Autodesk Fusion 360 part; units mm, degrees
(part 7 of 7)
sketch "Hex nut (1) (8)" plane through (0, 0, 57.8) normal (0, 0, 1) x (1, 0, 0) in component "HARDWARE | Core M2x50 · unthreaded reference"
  line L0 (2.3094, 42) -> (1.1547, 44)
  line L1 (1.1547, 44) -> (-1.1547, 44)
  line L2 (-1.1547, 44) -> (-2.3094, 42)
  line L3 (-2.3094, 42) -> (-1.1547, 40)
  line L4 (-1.1547, 40) -> (1.1547, 40)
  line L5 (1.1547, 40) -> (2.3094, 42)
extrude "Hex nut (2)'''''''" add sketch "Hex nut (1) (8)" along normal blind 1.6 separate body makes body 121 in component "HARDWARE | Core M2x50 · unthreaded reference"
ref_plane "WorkPlane12" through (0, 0, 57.8) normal (0, 0, 1) x (1, 0, 0) in component "HARDWARE | Core M2x50 · unthreaded reference"
sketch "Nut thread envelope clearance (1) (9)" plane through (0, 0, 57.8) normal (0, 0, 1) x (1, 0, 0) in component "HARDWARE | Core M2x50 · unthreaded reference"
  circle A0 centre (0, 42) radius 1.15
extrude "Nut thread envelope clearance (2)''''''''" cut sketch "Nut thread envelope clearance (1) (9)" along normal blind 1.6 bodies 121 in component "HARDWARE | Core M2x50 · unthreaded reference"
ref_plane "WorkPlane13" through (0, 0, 12) normal (0, 0, 1) x (1, 0, 0) in component "HARDWARE | Core M2x50 · unthreaded reference"
sketch "Bolt shank (2) (6)" plane through (0, 0, 12) normal (0, 0, 1) x (1, 0, 0) in component "HARDWARE | Core M2x50 · unthreaded reference"
  circle A0 centre (-36.3731, 21) radius 1
extrude "Bolt shank (3)''''" add sketch "Bolt shank (2) (6)" along normal blind 50 separate body makes body 122 in component "HARDWARE | Core M2x50 · unthreaded reference"
ref_plane "WorkPlane14" through (0, 0, 10) normal (0, 0, 1) x (1, 0, 0) in component "HARDWARE | Core M2x50 · unthreaded reference"
sketch "Socket head envelope (2) (6)" plane through (0, 0, 10) normal (0, 0, 1) x (1, 0, 0) in component "HARDWARE | Core M2x50 · unthreaded reference"
  circle A0 centre (-36.3731, 21) radius 1.9
extrude "Socket head envelope (3)''''" add sketch "Socket head envelope (2) (6)" along normal blind 2 bodies 122 in component "HARDWARE | Core M2x50 · unthreaded reference"
ref_plane "WorkPlane15" through (0, 0, 57.4) normal (0, 0, 1) x (1, 0, 0) in component "HARDWARE | Core M2x50 · unthreaded reference"
sketch "Washer (2) (6)" plane through (0, 0, 57.4) normal (0, 0, 1) x (1, 0, 0) in component "HARDWARE | Core M2x50 · unthreaded reference"
  circle A0 centre (-36.3731, 21) radius 2
extrude "Washer (3)''''" add sketch "Washer (2) (6)" along normal blind 0.4 separate body makes body 123 in component "HARDWARE | Core M2x50 · unthreaded reference"
ref_plane "WorkPlane16" through (0, 0, 57.4) normal (0, 0, 1) x (1, 0, 0) in component "HARDWARE | Core M2x50 · unthreaded reference"
sketch "Washer clearance (2) (6)" plane through (0, 0, 57.4) normal (0, 0, 1) x (1, 0, 0) in component "HARDWARE | Core M2x50 · unthreaded reference"
  circle A0 centre (-36.3731, 21) radius 1.2
extrude "Washer clearance (3)''''" cut sketch "Washer clearance (2) (6)" along normal blind 0.4 bodies 123 in component "HARDWARE | Core M2x50 · unthreaded reference"
ref_plane "WorkPlane17" through (0, 0, 57.8) normal (0, 0, 1) x (1, 0, 0) in component "HARDWARE | Core M2x50 · unthreaded reference"
sketch "Hex nut (2) (6)" plane through (0, 0, 57.8) normal (0, 0, 1) x (1, 0, 0) in component "HARDWARE | Core M2x50 · unthreaded reference"
  line L0 (-34.0637, 21) -> (-35.2184, 23)
  line L1 (-35.2184, 23) -> (-37.5278, 23)
  line L2 (-37.5278, 23) -> (-38.6825, 21)
  line L3 (-38.6825, 21) -> (-37.5278, 19)
  line L4 (-37.5278, 19) -> (-35.2184, 19)
  line L5 (-35.2184, 19) -> (-34.0637, 21)
extrude "Hex nut (3)''''" add sketch "Hex nut (2) (6)" along normal blind 1.6 separate body makes body 124 in component "HARDWARE | Core M2x50 · unthreaded reference"
ref_plane "WorkPlane18" through (0, 0, 57.8) normal (0, 0, 1) x (1, 0, 0) in component "HARDWARE | Core M2x50 · unthreaded reference"
sketch "Nut thread envelope clearance (2) (6)" plane through (0, 0, 57.8) normal (0, 0, 1) x (1, 0, 0) in component "HARDWARE | Core M2x50 · unthreaded reference"
  circle A0 centre (-36.3731, 21) radius 1.15
extrude "Nut thread envelope clearance (3)''''" cut sketch "Nut thread envelope clearance (2) (6)" along normal blind 1.6 bodies 124 in component "HARDWARE | Core M2x50 · unthreaded reference"
ref_plane "WorkPlane19" through (0, 0, 12) normal (0, 0, 1) x (1, 0, 0) in component "HARDWARE | Core M2x50 · unthreaded reference"
sketch "Bolt shank (3) (6)" plane through (0, 0, 12) normal (0, 0, 1) x (1, 0, 0) in component "HARDWARE | Core M2x50 · unthreaded reference"
  circle A0 centre (-36.3731, -21) radius 1
extrude "Bolt shank (4)''''" add sketch "Bolt shank (3) (6)" along normal blind 50 separate body makes body 125 in component "HARDWARE | Core M2x50 · unthreaded reference"
ref_plane "WorkPlane20" through (0, 0, 10) normal (0, 0, 1) x (1, 0, 0) in component "HARDWARE | Core M2x50 · unthreaded reference"
sketch "Socket head envelope (3) (6)" plane through (0, 0, 10) normal (0, 0, 1) x (1, 0, 0) in component "HARDWARE | Core M2x50 · unthreaded reference"
  circle A0 centre (-36.3731, -21) radius 1.9
extrude "Socket head envelope (4)''''" add sketch "Socket head envelope (3) (6)" along normal blind 2 bodies 125 in component "HARDWARE | Core M2x50 · unthreaded reference"
ref_plane "WorkPlane21" through (0, 0, 57.4) normal (0, 0, 1) x (1, 0, 0) in component "HARDWARE | Core M2x50 · unthreaded reference"
sketch "Washer (3) (6)" plane through (0, 0, 57.4) normal (0, 0, 1) x (1, 0, 0) in component "HARDWARE | Core M2x50 · unthreaded reference"
  circle A0 centre (-36.3731, -21) radius 2
extrude "Washer (4)''''" add sketch "Washer (3) (6)" along normal blind 0.4 separate body makes body 126 in component "HARDWARE | Core M2x50 · unthreaded reference"
ref_plane "WorkPlane22" through (0, 0, 57.4) normal (0, 0, 1) x (1, 0, 0) in component "HARDWARE | Core M2x50 · unthreaded reference"
sketch "Washer clearance (3) (6)" plane through (0, 0, 57.4) normal (0, 0, 1) x (1, 0, 0) in component "HARDWARE | Core M2x50 · unthreaded reference"
  circle A0 centre (-36.3731, -21) radius 1.2
extrude "Washer clearance (4)''''" cut sketch "Washer clearance (3) (6)" along normal blind 0.4 bodies 126 in component "HARDWARE | Core M2x50 · unthreaded reference"
ref_plane "WorkPlane23" through (0, 0, 57.8) normal (0, 0, 1) x (1, 0, 0) in component "HARDWARE | Core M2x50 · unthreaded reference"
sketch "Hex nut (3) (6)" plane through (0, 0, 57.8) normal (0, 0, 1) x (1, 0, 0) in component "HARDWARE | Core M2x50 · unthreaded reference"
  line L0 (-34.0637, -21) -> (-35.2184, -19)
  line L1 (-35.2184, -19) -> (-37.5278, -19)
  line L2 (-37.5278, -19) -> (-38.6825, -21)
  line L3 (-38.6825, -21) -> (-37.5278, -23)
  line L4 (-37.5278, -23) -> (-35.2184, -23)
  line L5 (-35.2184, -23) -> (-34.0637, -21)
extrude "Hex nut (4)''''" add sketch "Hex nut (3) (6)" along normal blind 1.6 separate body makes body 127 in component "HARDWARE | Core M2x50 · unthreaded reference"
ref_plane "WorkPlane24" through (0, 0, 57.8) normal (0, 0, 1) x (1, 0, 0) in component "HARDWARE | Core M2x50 · unthreaded reference"
sketch "Nut thread envelope clearance (3) (6)" plane through (0, 0, 57.8) normal (0, 0, 1) x (1, 0, 0) in component "HARDWARE | Core M2x50 · unthreaded reference"
  circle A0 centre (-36.3731, -21) radius 1.15
extrude "Nut thread envelope clearance (4)''''" cut sketch "Nut thread envelope clearance (3) (6)" along normal blind 1.6 bodies 127 in component "HARDWARE | Core M2x50 · unthreaded reference"
ref_plane "WorkPlane25" through (0, 0, 12) normal (0, 0, 1) x (1, 0, 0) in component "HARDWARE | Core M2x50 · unthreaded reference"
sketch "Bolt shank (4) (4)" plane through (0, 0, 12) normal (0, 0, 1) x (1, 0, 0) in component "HARDWARE | Core M2x50 · unthreaded reference"
  circle A0 centre (0, -42) radius 1
extrude "Bolt shank (5)''" add sketch "Bolt shank (4) (4)" along normal blind 50 separate body makes body 128 in component "HARDWARE | Core M2x50 · unthreaded reference"
ref_plane "WorkPlane26" through (0, 0, 10) normal (0, 0, 1) x (1, 0, 0) in component "HARDWARE | Core M2x50 · unthreaded reference"
sketch "Socket head envelope (4) (4)" plane through (0, 0, 10) normal (0, 0, 1) x (1, 0, 0) in component "HARDWARE | Core M2x50 · unthreaded reference"
  circle A0 centre (0, -42) radius 1.9
extrude "Socket head envelope (5)''" add sketch "Socket head envelope (4) (4)" along normal blind 2 bodies 128 in component "HARDWARE | Core M2x50 · unthreaded reference"
ref_plane "WorkPlane27" through (0, 0, 57.4) normal (0, 0, 1) x (1, 0, 0) in component "HARDWARE | Core M2x50 · unthreaded reference"
sketch "Washer (4) (4)" plane through (0, 0, 57.4) normal (0, 0, 1) x (1, 0, 0) in component "HARDWARE | Core M2x50 · unthreaded reference"
  circle A0 centre (0, -42) radius 2
extrude "Washer (5)''" add sketch "Washer (4) (4)" along normal blind 0.4 separate body makes body 129 in component "HARDWARE | Core M2x50 · unthreaded reference"
ref_plane "WorkPlane28" through (0, 0, 57.4) normal (0, 0, 1) x (1, 0, 0) in component "HARDWARE | Core M2x50 · unthreaded reference"
sketch "Washer clearance (4) (4)" plane through (0, 0, 57.4) normal (0, 0, 1) x (1, 0, 0) in component "HARDWARE | Core M2x50 · unthreaded reference"
  circle A0 centre (0, -42) radius 1.2
extrude "Washer clearance (5)''" cut sketch "Washer clearance (4) (4)" along normal blind 0.4 bodies 129 in component "HARDWARE | Core M2x50 · unthreaded reference"
ref_plane "WorkPlane29" through (0, 0, 57.8) normal (0, 0, 1) x (1, 0, 0) in component "HARDWARE | Core M2x50 · unthreaded reference"
sketch "Hex nut (4) (4)" plane through (0, 0, 57.8) normal (0, 0, 1) x (1, 0, 0) in component "HARDWARE | Core M2x50 · unthreaded reference"
  line L0 (2.3094, -42) -> (1.1547, -40)
  line L1 (1.1547, -40) -> (-1.1547, -40)
  line L2 (-1.1547, -40) -> (-2.3094, -42)
  line L3 (-2.3094, -42) -> (-1.1547, -44)
  line L4 (-1.1547, -44) -> (1.1547, -44)
  line L5 (1.1547, -44) -> (2.3094, -42)
extrude "Hex nut (5)''" add sketch "Hex nut (4) (4)" along normal blind 1.6 separate body makes body 130 in component "HARDWARE | Core M2x50 · unthreaded reference"
ref_plane "WorkPlane30" through (0, 0, 57.8) normal (0, 0, 1) x (1, 0, 0) in component "HARDWARE | Core M2x50 · unthreaded reference"
sketch "Nut thread envelope clearance (4) (4)" plane through (0, 0, 57.8) normal (0, 0, 1) x (1, 0, 0) in component "HARDWARE | Core M2x50 · unthreaded reference"
  circle A0 centre (0, -42) radius 1.15
extrude "Nut thread envelope clearance (5)''" cut sketch "Nut thread envelope clearance (4) (4)" along normal blind 1.6 bodies 130 in component "HARDWARE | Core M2x50 · unthreaded reference"
ref_plane "WorkPlane31" through (0, 0, 12) normal (0, 0, 1) x (1, 0, 0) in component "HARDWARE | Core M2x50 · unthreaded reference"
sketch "Bolt shank (5) (3)" plane through (0, 0, 12) normal (0, 0, 1) x (1, 0, 0) in component "HARDWARE | Core M2x50 · unthreaded reference"
  circle A0 centre (36.3731, -21) radius 1
extrude "Bolt shank (6)''" add sketch "Bolt shank (5) (3)" along normal blind 50 separate body makes body 131 in component "HARDWARE | Core M2x50 · unthreaded reference"
ref_plane "WorkPlane32" through (0, 0, 10) normal (0, 0, 1) x (1, 0, 0) in component "HARDWARE | Core M2x50 · unthreaded reference"
sketch "Socket head envelope (5) (3)" plane through (0, 0, 10) normal (0, 0, 1) x (1, 0, 0) in component "HARDWARE | Core M2x50 · unthreaded reference"
  circle A0 centre (36.3731, -21) radius 1.9
extrude "Socket head envelope (6)''" add sketch "Socket head envelope (5) (3)" along normal blind 2 bodies 131 in component "HARDWARE | Core M2x50 · unthreaded reference"
ref_plane "WorkPlane33" through (0, 0, 57.4) normal (0, 0, 1) x (1, 0, 0) in component "HARDWARE | Core M2x50 · unthreaded reference"
sketch "Washer (5) (3)" plane through (0, 0, 57.4) normal (0, 0, 1) x (1, 0, 0) in component "HARDWARE | Core M2x50 · unthreaded reference"
  circle A0 centre (36.3731, -21) radius 2
extrude "Washer (6)''" add sketch "Washer (5) (3)" along normal blind 0.4 separate body makes body 132 in component "HARDWARE | Core M2x50 · unthreaded reference"
ref_plane "WorkPlane34" through (0, 0, 57.4) normal (0, 0, 1) x (1, 0, 0) in component "HARDWARE | Core M2x50 · unthreaded reference"
sketch "Washer clearance (5) (4)" plane through (0, 0, 57.4) normal (0, 0, 1) x (1, 0, 0) in component "HARDWARE | Core M2x50 · unthreaded reference"
  circle A0 centre (36.3731, -21) radius 1.2
extrude "Washer clearance (6)''" cut sketch "Washer clearance (5) (4)" along normal blind 0.4 bodies 132 in component "HARDWARE | Core M2x50 · unthreaded reference"
ref_plane "WorkPlane35" through (0, 0, 57.8) normal (0, 0, 1) x (1, 0, 0) in component "HARDWARE | Core M2x50 · unthreaded reference"
sketch "Hex nut (5) (3)" plane through (0, 0, 57.8) normal (0, 0, 1) x (1, 0, 0) in component "HARDWARE | Core M2x50 · unthreaded reference"
  line L0 (38.6825, -21) -> (37.5278, -19)
  line L1 (37.5278, -19) -> (35.2184, -19)
  line L2 (35.2184, -19) -> (34.0637, -21)
  line L3 (34.0637, -21) -> (35.2184, -23)
  line L4 (35.2184, -23) -> (37.5278, -23)
  line L5 (37.5278, -23) -> (38.6825, -21)
extrude "Hex nut (6)''" add sketch "Hex nut (5) (3)" along normal blind 1.6 separate body makes body 133 in component "HARDWARE | Core M2x50 · unthreaded reference"
ref_plane "WorkPlane36" through (0, 0, 57.8) normal (0, 0, 1) x (1, 0, 0) in component "HARDWARE | Core M2x50 · unthreaded reference"
sketch "Nut thread envelope clearance (5) (4)" plane through (0, 0, 57.8) normal (0, 0, 1) x (1, 0, 0) in component "HARDWARE | Core M2x50 · unthreaded reference"
  circle A0 centre (36.3731, -21) radius 1.15
extrude "Nut thread envelope clearance (6)''" cut sketch "Nut thread envelope clearance (5) (4)" along normal blind 1.6 bodies 133 in component "HARDWARE | Core M2x50 · unthreaded reference"
ref_plane "WorkPlane27" through (0, 0, -9) normal (0, 0, 1) x (1, 0, 0) in component "01 | Chassis · ground"
sketch "Regulator M2 socket head insertion access" plane through (0, 0, -9) normal (0, 0, 1) x (1, 0, 0) in component "01 | Chassis · ground"
  circle A0 centre (-13.716, -19.431) radius 2.1
  circle A1 centre (11.684, -19.431) radius 2.1
  circle A2 centre (-13.716, 19.431) radius 2.1
  circle A3 centre (11.684, 19.431) radius 2.1
extrude "Regulator M2 socket head insertion access (1)" cut sketch "Regulator M2 socket head insertion access" along normal blind 3 bodies 1 in component "01 | Chassis · ground"
ref_plane "WorkPlane14" through (0, 0, -6) normal (0, 0, 1) x (1, 0, 0) in component "CORE | PowerShelf"
sketch "Yaw servo ear service clearance" plane through (0, 0, -6) normal (0, 0, 1) x (1, 0, 0) in component "CORE | PowerShelf"
  line L0 (19.5524, 20.4657) -> (36.4524, 49.7374)
  line L1 (36.4524, 49.7374) -> (24.8476, 56.4374)
  line L2 (24.8476, 56.4374) -> (7.9476, 27.1657)
  line L3 (7.9476, 27.1657) -> (19.5524, 20.4657)
extrude "Yaw servo ear service clearance (1)" cut sketch "Yaw servo ear service clearance" along normal blind 3 bodies 3 in component "CORE | PowerShelf"
ref_plane "WorkPlane15" through (0, 0, -6) normal (0, 0, 1) x (1, 0, 0) in component "CORE | PowerShelf"
sketch "Yaw servo ear service clearance (1)" plane through (0, 0, -6) normal (0, 0, 1) x (1, 0, 0) in component "CORE | PowerShelf"
  line L0 (-7.9476, 27.1657) -> (-24.8476, 56.4374)
  line L1 (-24.8476, 56.4374) -> (-36.4524, 49.7374)
  line L2 (-36.4524, 49.7374) -> (-19.5524, 20.4657)
  line L3 (-19.5524, 20.4657) -> (-7.9476, 27.1657)
extrude "Yaw servo ear service clearance (2)" cut sketch "Yaw servo ear service clearance (1)" along normal blind 3 bodies 3 in component "CORE | PowerShelf"
ref_plane "WorkPlane16" through (0, 0, -6) normal (0, 0, 1) x (1, 0, 0) in component "CORE | PowerShelf"
sketch "Yaw servo ear service clearance (2)" plane through (0, 0, -6) normal (0, 0, 1) x (1, 0, 0) in component "CORE | PowerShelf"
  line L0 (-19.5524, -20.4657) -> (-36.4524, -49.7374)
  line L1 (-36.4524, -49.7374) -> (-24.8476, -56.4374)
  line L2 (-24.8476, -56.4374) -> (-7.9476, -27.1657)
  line L3 (-7.9476, -27.1657) -> (-19.5524, -20.4657)
extrude "Yaw servo ear service clearance (3)" cut sketch "Yaw servo ear service clearance (2)" along normal blind 3 bodies 3 in component "CORE | PowerShelf"
ref_plane "WorkPlane17" through (0, 0, -6) normal (0, 0, 1) x (1, 0, 0) in component "CORE | PowerShelf"
sketch "Yaw servo ear service clearance (3)" plane through (0, 0, -6) normal (0, 0, 1) x (1, 0, 0) in component "CORE | PowerShelf"
  line L0 (7.9476, -27.1657) -> (24.8476, -56.4374)
  line L1 (24.8476, -56.4374) -> (36.4524, -49.7374)
  line L2 (36.4524, -49.7374) -> (19.5524, -20.4657)
  line L3 (19.5524, -20.4657) -> (7.9476, -27.1657)
extrude "Yaw servo ear service clearance (4)" cut sketch "Yaw servo ear service clearance (3)" along normal blind 3 bodies 3 in component "CORE | PowerShelf"
ref_plane "WorkPlane25" through (0, 0, 2) normal (0, 0, 1) x (1, 0, 0) in component "HARDWARE | Servo buck M2x10 · unthreaded reference"
sketch "M2x10 complete nut engagement" plane through (0, 0, 2) normal (0, 0, 1) x (1, 0, 0) in component "HARDWARE | Servo buck M2x10 · unthreaded reference"
  circle A0 centre (-13.716, -19.431) radius 1
extrude "M2x10 complete nut engagement (1)" add sketch "M2x10 complete nut engagement" along normal blind 2 bodies 104 in component "HARDWARE | Servo buck M2x10 · unthreaded reference"
ref_plane "WorkPlane26" through (0, 0, 2) normal (0, 0, 1) x (1, 0, 0) in component "HARDWARE | Servo buck M2x10 · unthreaded reference"
sketch "M2x10 complete nut engagement (1)" plane through (0, 0, 2) normal (0, 0, 1) x (1, 0, 0) in component "HARDWARE | Servo buck M2x10 · unthreaded reference"
  circle A0 centre (11.684, -19.431) radius 1
extrude "M2x10 complete nut engagement (2)" add sketch "M2x10 complete nut engagement (1)" along normal blind 2 bodies 107 in component "HARDWARE | Servo buck M2x10 · unthreaded reference"
ref_plane "WorkPlane27" through (0, 0, 2) normal (0, 0, 1) x (1, 0, 0) in component "HARDWARE | Servo buck M2x10 · unthreaded reference"
sketch "M2x10 complete nut engagement (2)" plane through (0, 0, 2) normal (0, 0, 1) x (1, 0, 0) in component "HARDWARE | Servo buck M2x10 · unthreaded reference"
  circle A0 centre (-13.716, 19.431) radius 1
extrude "M2x10 complete nut engagement (3)" add sketch "M2x10 complete nut engagement (2)" along normal blind 2 bodies 110 in component "HARDWARE | Servo buck M2x10 · unthreaded reference"
ref_plane "WorkPlane28" through (0, 0, 2) normal (0, 0, 1) x (1, 0, 0) in component "HARDWARE | Servo buck M2x10 · unthreaded reference"
sketch "M2x10 complete nut engagement (3)" plane through (0, 0, 2) normal (0, 0, 1) x (1, 0, 0) in component "HARDWARE | Servo buck M2x10 · unthreaded reference"
  circle A0 centre (11.684, 19.431) radius 1
extrude "M2x10 complete nut engagement (4)" add sketch "M2x10 complete nut engagement (3)" along normal blind 2 bodies 113 in component "HARDWARE | Servo buck M2x10 · unthreaded reference"
ref_plane "WorkPlane10" through (0, 0, 55) normal (0, 0, 1) x (1, 0, 0) in component "CORE | CoreCap"
sketch "Reinforced removable cap screw boss" plane through (0, 0, 55) normal (0, 0, 1) x (1, 0, 0) in component "CORE | CoreCap"
  circle A0 centre (36.3731, 21) radius 4
extrude "Reinforced removable cap screw boss (1)" add sketch "Reinforced removable cap screw boss" along normal blind 2.4 bodies 11 in component "CORE | CoreCap"
ref_plane "WorkPlane11" through (0, 0, 55) normal (0, 0, 1) x (1, 0, 0) in component "CORE | CoreCap"
sketch "Reinforced removable cap screw boss (1)" plane through (0, 0, 55) normal (0, 0, 1) x (1, 0, 0) in component "CORE | CoreCap"
  circle A0 centre (0, 42) radius 4
extrude "Reinforced removable cap screw boss (2)" add sketch "Reinforced removable cap screw boss (1)" along normal blind 2.4 bodies 11 in component "CORE | CoreCap"
ref_plane "WorkPlane12" through (0, 0, 55) normal (0, 0, 1) x (1, 0, 0) in component "CORE | CoreCap"
sketch "Reinforced removable cap screw boss (2)" plane through (0, 0, 55) normal (0, 0, 1) x (1, 0, 0) in component "CORE | CoreCap"
  circle A0 centre (-36.3731, 21) radius 4
extrude "Reinforced removable cap screw boss (3)" add sketch "Reinforced removable cap screw boss (2)" along normal blind 2.4 bodies 11 in component "CORE | CoreCap"
ref_plane "WorkPlane13" through (0, 0, 55) normal (0, 0, 1) x (1, 0, 0) in component "CORE | CoreCap"
sketch "Reinforced removable cap screw boss (3)" plane through (0, 0, 55) normal (0, 0, 1) x (1, 0, 0) in component "CORE | CoreCap"
  circle A0 centre (-36.3731, -21) radius 4
extrude "Reinforced removable cap screw boss (4)" add sketch "Reinforced removable cap screw boss (3)" along normal blind 2.4 bodies 11 in component "CORE | CoreCap"
ref_plane "WorkPlane14" through (0, 0, 55) normal (0, 0, 1) x (1, 0, 0) in component "CORE | CoreCap"
sketch "Reinforced removable cap screw boss (4)" plane through (0, 0, 55) normal (0, 0, 1) x (1, 0, 0) in component "CORE | CoreCap"
  circle A0 centre (0, -42) radius 4
extrude "Reinforced removable cap screw boss (5)" add sketch "Reinforced removable cap screw boss (4)" along normal blind 2.4 bodies 11 in component "CORE | CoreCap"
ref_plane "WorkPlane15" through (0, 0, 55) normal (0, 0, 1) x (1, 0, 0) in component "CORE | CoreCap"
sketch "Reinforced removable cap screw boss (5)" plane through (0, 0, 55) normal (0, 0, 1) x (1, 0, 0) in component "CORE | CoreCap"
  circle A0 centre (36.3731, -21) radius 4
extrude "Reinforced removable cap screw boss (6)" add sketch "Reinforced removable cap screw boss (5)" along normal blind 2.4 bodies 11 in component "CORE | CoreCap"
ref_plane "WorkPlane16" through (0, 0, 55) normal (0, 0, 1) x (1, 0, 0) in component "CORE | CoreCap"
sketch "M2 cap through holes" plane through (0, 0, 55) normal (0, 0, 1) x (1, 0, 0) in component "CORE | CoreCap"
  circle A0 centre (36.3731, 21) radius 1.2
  circle A1 centre (0, 42) radius 1.2
  circle A2 centre (-36.3731, 21) radius 1.2
  circle A3 centre (-36.3731, -21) radius 1.2
  circle A4 centre (0, -42) radius 1.2
  circle A5 centre (36.3731, -21) radius 1.2
extrude "M2 cap through holes (1)" cut sketch "M2 cap through holes" along normal blind 2.4 bodies 11 in component "CORE | CoreCap"
component "01 | Chassis · ground" placed x (1, 0, 0) y (0, 1, 0) z (0, 0, 1) at (0, 0, 0)
component "CORE | LowerDeck" placed x (1, 0, 0) y (0, 1, 0) z (0, 0, 1) at (0, 0, 0)
component "CORE | PowerShelf" placed x (1, 0, 0) y (0, 1, 0) z (0, 0, 1) at (0, 0, 0)
component "CORE | ElectronicsDeck" placed x (1, 0, 0) y (0, 1, 0) z (0, 0, 1) at (0, 0, 0)
component "CORE | LowerSpacer" placed x (1, 0, 0) y (0, 1, 0) z (0, 0, 1) at (27.7128, 16, 0)
component "CORE | UpperSpacer" placed x (1, 0, 0) y (0, 1, 0) z (0, 0, 1) at (27.7128, 16, 0)
component "CORE | GuardLower" placed x (1, 0, 0) y (0, 1, 0) z (0, 0, 1) at (36.3731, 21, 0)
component "CORE | GuardUpper" placed x (1, 0, 0) y (0, 1, 0) z (0, 0, 1) at (36.3731, 21, 0)
component "CORE | GuardTall" placed x (1, 0, 0) y (0, 1, 0) z (0, 0, 1) at (0, 42, 0)
component "CORE | CoreBridge" placed x (1, 0, 0) y (0, 1, 0) z (0, 0, 1) at (0, 0, 0)
component "CORE | CoreCap" placed x (1, 0, 0) y (0, 1, 0) z (0, 0, 1) at (0, 0, 0)
component "03 | Coxa yaw plate" placed x (1, 0, 0) y (0, 1, 0) z (0, 0, 1) at (49, 0, 0)
component "04 | Hip removable servo bracket" placed x (1, 0, 0) y (0, 1, 0) z (0, 0, 1) at (49, 0, 0)
component "05 | Femur horn link" placed x (0.906308, 0, -0.422618) y (0, 1, 0) z (0.422618, 0, 0.906308) at (79, 0, 38)
component "06 | Knee servo mount" placed x (0.906308, 0, -0.422618) y (0, 1, 0) z (0.422618, 0, 0.906308) at (79, 0, 38)
component "07 | Tibia · tapered foot" placed x (-0.087156, 0, -0.996195) y (0, 1, 0) z (0.996195, 0, -0.087156) at (117.0649, 0, 20.25)
component "MG90S | case envelope · measure actual ears" placed x (1, 0, 0) y (0, 1, 0) z (0, 0, 1) at (49, 0, 0)
component "Stock double horn | reference only" placed x (1, 0, 0) y (0, 1, 0) z (0, 0, 1) at (49, 0, 0)
component "FIT TEST ONLY · servo and horn coupon" placed x (1, 0, 0) y (0, 1, 0) z (0, 0, 1) at (0, 0, 0)
component "MG90S | case envelope · measure actual ears" placed x (1, 0, 0) y (0, 0, -1) z (0, 1, 0) at (79, 0, 38)
component "Stock double horn | reference only" placed x (0.906308, 0, -0.422618) y (-0.422618, 0, -0.906308) z (0, 1, 0) at (79, 0, 38)
component "MG90S | case envelope · measure actual ears" placed x (0.906308, 0, -0.422618) y (0.422618, 0, 0.906308) z (0, -1, 0) at (117.0649, 19, 20.25)
component "Stock double horn | reference only" placed x (-0.087156, 0, -0.996195) y (0.996195, 0, -0.087156) z (0, -1, 0) at (117.0649, 19, 20.25)
component "CORE | LowerSpacer" placed x (1, 0, 0) y (0, 1, 0) z (0, 0, 1) at (0, 32, 0)
component "CORE | UpperSpacer" placed x (1, 0, 0) y (0, 1, 0) z (0, 0, 1) at (0, 32, 0)
component "MG90S | case envelope · measure actual ears" placed x (0.5, 0.866025, 0) y (-0.866025, 0.5, 0) z (0, 0, 1) at (24.5, 42.4352, 0)
component "03 | Coxa yaw plate" placed x (0.5, 0.866025, 0) y (-0.866025, 0.5, 0) z (0, 0, 1) at (24.5, 42.4352, 0)
component "04 | Hip removable servo bracket" placed x (0.5, 0.866025, 0) y (-0.866025, 0.5, 0) z (0, 0, 1) at (24.5, 42.4352, 0)
component "Stock double horn | reference only" placed x (0.5, 0.866025, 0) y (-0.866025, 0.5, 0) z (0, 0, 1) at (24.5, 42.4352, 0)
component "MG90S | case envelope · measure actual ears" placed x (0.5, 0.866025, 0) y (0, 0, -1) z (-0.866025, 0.5, 0) at (39.5, 68.416, 38)
component "05 | Femur horn link" placed x (0.453154, 0.784886, -0.422618) y (-0.866025, 0.5, 0) z (0.211309, 0.365998, 0.906308) at (39.5, 68.416, 38)
component "06 | Knee servo mount" placed x (0.453154, 0.784886, -0.422618) y (-0.866025, 0.5, 0) z (0.211309, 0.365998, 0.906308) at (39.5, 68.416, 38)
component "Stock double horn | reference only" placed x (0.453154, 0.784886, -0.422618) y (-0.211309, -0.365998, -0.906308) z (-0.866025, 0.5, 0) at (39.5, 68.416, 38)
component "MG90S | case envelope · measure actual ears" placed x (0.453154, 0.784886, -0.422618) y (0.211309, 0.365998, 0.906308) z (0.866025, -0.5, 0) at (42.078, 110.8812, 20.25)
component "07 | Tibia · tapered foot" placed x (-0.043578, -0.075479, -0.996195) y (-0.866025, 0.5, 0) z (0.498097, 0.86273, -0.087156) at (58.5325, 101.3812, 20.25)
component "Stock double horn | reference only" placed x (-0.043578, -0.075479, -0.996195) y (0.498097, 0.86273, -0.087156) z (0.866025, -0.5, 0) at (42.078, 110.8812, 20.25)
component "CORE | LowerSpacer" placed x (1, 0, 0) y (0, 1, 0) z (0, 0, 1) at (-27.7128, 16, 0)
component "CORE | UpperSpacer" placed x (1, 0, 0) y (0, 1, 0) z (0, 0, 1) at (-27.7128, 16, 0)
component "MG90S | case envelope · measure actual ears" placed x (-0.5, 0.866025, 0) y (-0.866025, -0.5, 0) z (0, 0, 1) at (-24.5, 42.4352, 0)
component "03 | Coxa yaw plate" placed x (-0.5, 0.866025, 0) y (-0.866025, -0.5, 0) z (0, 0, 1) at (-24.5, 42.4352, 0)
component "04 | Hip removable servo bracket" placed x (-0.5, 0.866025, 0) y (-0.866025, -0.5, 0) z (0, 0, 1) at (-24.5, 42.4352, 0)
component "Stock double horn | reference only" placed x (-0.5, 0.866025, 0) y (-0.866025, -0.5, 0) z (0, 0, 1) at (-24.5, 42.4352, 0)
component "MG90S | case envelope · measure actual ears" placed x (-0.5, 0.866025, 0) y (0, 0, -1) z (-0.866025, -0.5, 0) at (-39.5, 68.416, 38)
component "05 | Femur horn link" placed x (-0.453154, 0.784886, -0.422618) y (-0.866025, -0.5, 0) z (-0.211309, 0.365998, 0.906308) at (-39.5, 68.416, 38)
component "06 | Knee servo mount" placed x (-0.453154, 0.784886, -0.422618) y (-0.866025, -0.5, 0) z (-0.211309, 0.365998, 0.906308) at (-39.5, 68.416, 38)
component "Stock double horn | reference only" placed x (-0.453154, 0.784886, -0.422618) y (0.211309, -0.365998, -0.906308) z (-0.866025, -0.5, 0) at (-39.5, 68.416, 38)
component "MG90S | case envelope · measure actual ears" placed x (-0.453154, 0.784886, -0.422618) y (-0.211309, 0.365998, 0.906308) z (0.866025, 0.5, 0) at (-74.9869, 91.8812, 20.25)
component "07 | Tibia · tapered foot" placed x (0.043578, -0.075479, -0.996195) y (-0.866025, -0.5, 0) z (-0.498097, 0.86273, -0.087156) at (-58.5325, 101.3812, 20.25)
component "Stock double horn | reference only" placed x (0.043578, -0.075479, -0.996195) y (-0.498097, 0.86273, -0.087156) z (0.866025, 0.5, 0) at (-74.9869, 91.8812, 20.25)
component "CORE | LowerSpacer" placed x (1, 0, 0) y (0, 1, 0) z (0, 0, 1) at (-27.7128, -16, 0)
component "CORE | UpperSpacer" placed x (1, 0, 0) y (0, 1, 0) z (0, 0, 1) at (-27.7128, -16, 0)
component "MG90S | case envelope · measure actual ears" placed x (-1, 0, 0) y (0, -1, 0) z (0, 0, 1) at (-49, 0, 0)
component "03 | Coxa yaw plate" placed x (-1, 0, 0) y (0, -1, 0) z (0, 0, 1) at (-49, 0, 0)
component "04 | Hip removable servo bracket" placed x (-1, 0, 0) y (0, -1, 0) z (0, 0, 1) at (-49, 0, 0)
component "Stock double horn | reference only" placed x (-1, 0, 0) y (0, -1, 0) z (0, 0, 1) at (-49, 0, 0)
component "MG90S | case envelope · measure actual ears" placed x (-1, 0, 0) y (0, 0, -1) z (0, -1, 0) at (-79, 0, 38)
component "05 | Femur horn link" placed x (-0.906308, 0, -0.422618) y (0, -1, 0) z (-0.422618, 0, 0.906308) at (-79, 0, 38)
component "06 | Knee servo mount" placed x (-0.906308, 0, -0.422618) y (0, -1, 0) z (-0.422618, 0, 0.906308) at (-79, 0, 38)
component "Stock double horn | reference only" placed x (-0.906308, 0, -0.422618) y (0.422618, 0, -0.906308) z (0, -1, 0) at (-79, 0, 38)
component "MG90S | case envelope · measure actual ears" placed x (-0.906308, 0, -0.422618) y (-0.422618, 0, 0.906308) z (0, 1, 0) at (-117.0649, -19, 20.25)
component "07 | Tibia · tapered foot" placed x (0.087156, 0, -0.996195) y (0, -1, 0) z (-0.996195, 0, -0.087156) at (-117.0649, 0, 20.25)
component "Stock double horn | reference only" placed x (0.087156, 0, -0.996195) y (-0.996195, 0, -0.087156) z (0, 1, 0) at (-117.0649, -19, 20.25)
component "CORE | LowerSpacer" placed x (1, 0, 0) y (0, 1, 0) z (0, 0, 1) at (0, -32, 0)
component "CORE | UpperSpacer" placed x (1, 0, 0) y (0, 1, 0) z (0, 0, 1) at (0, -32, 0)
component "MG90S | case envelope · measure actual ears" placed x (-0.5, -0.866025, 0) y (0.866025, -0.5, 0) z (0, 0, 1) at (-24.5, -42.4352, 0)
component "03 | Coxa yaw plate" placed x (-0.5, -0.866025, 0) y (0.866025, -0.5, 0) z (0, 0, 1) at (-24.5, -42.4352, 0)
component "04 | Hip removable servo bracket" placed x (-0.5, -0.866025, 0) y (0.866025, -0.5, 0) z (0, 0, 1) at (-24.5, -42.4352, 0)
component "Stock double horn | reference only" placed x (-0.5, -0.866025, 0) y (0.866025, -0.5, 0) z (0, 0, 1) at (-24.5, -42.4352, 0)
component "MG90S | case envelope · measure actual ears" placed x (-0.5, -0.866025, 0) y (0, 0, -1) z (0.866025, -0.5, 0) at (-39.5, -68.416, 38)
component "05 | Femur horn link" placed x (-0.453154, -0.784886, -0.422618) y (0.866025, -0.5, 0) z (-0.211309, -0.365998, 0.906308) at (-39.5, -68.416, 38)
component "06 | Knee servo mount" placed x (-0.453154, -0.784886, -0.422618) y (0.866025, -0.5, 0) z (-0.211309, -0.365998, 0.906308) at (-39.5, -68.416, 38)
component "Stock double horn | reference only" placed x (-0.453154, -0.784886, -0.422618) y (0.211309, 0.365998, -0.906308) z (0.866025, -0.5, 0) at (-39.5, -68.416, 38)
component "MG90S | case envelope · measure actual ears" placed x (-0.453154, -0.784886, -0.422618) y (-0.211309, -0.365998, 0.906308) z (-0.866025, 0.5, 0) at (-42.078, -110.8812, 20.25)
component "07 | Tibia · tapered foot" placed x (0.043578, 0.075479, -0.996195) y (0.866025, -0.5, 0) z (-0.498097, -0.86273, -0.087156) at (-58.5325, -101.3812, 20.25)
component "Stock double horn | reference only" placed x (0.043578, 0.075479, -0.996195) y (-0.498097, -0.86273, -0.087156) z (-0.866025, 0.5, 0) at (-42.078, -110.8812, 20.25)
component "CORE | LowerSpacer" placed x (1, 0, 0) y (0, 1, 0) z (0, 0, 1) at (27.7128, -16, 0)
component "CORE | UpperSpacer" placed x (1, 0, 0) y (0, 1, 0) z (0, 0, 1) at (27.7128, -16, 0)
component "MG90S | case envelope · measure actual ears" placed x (0.5, -0.866025, 0) y (0.866025, 0.5, 0) z (0, 0, 1) at (24.5, -42.4352, 0)
component "03 | Coxa yaw plate" placed x (0.5, -0.866025, 0) y (0.866025, 0.5, 0) z (0, 0, 1) at (24.5, -42.4352, 0)
component "04 | Hip removable servo bracket" placed x (0.5, -0.866025, 0) y (0.866025, 0.5, 0) z (0, 0, 1) at (24.5, -42.4352, 0)
component "Stock double horn | reference only" placed x (0.5, -0.866025, 0) y (0.866025, 0.5, 0) z (0, 0, 1) at (24.5, -42.4352, 0)
component "MG90S | case envelope · measure actual ears" placed x (0.5, -0.866025, 0) y (0, 0, -1) z (0.866025, 0.5, 0) at (39.5, -68.416, 38)
component "05 | Femur horn link" placed x (0.453154, -0.784886, -0.422618) y (0.866025, 0.5, 0) z (0.211309, -0.365998, 0.906308) at (39.5, -68.416, 38)
component "06 | Knee servo mount" placed x (0.453154, -0.784886, -0.422618) y (0.866025, 0.5, 0) z (0.211309, -0.365998, 0.906308) at (39.5, -68.416, 38)
component "Stock double horn | reference only" placed x (0.453154, -0.784886, -0.422618) y (-0.211309, 0.365998, -0.906308) z (0.866025, 0.5, 0) at (39.5, -68.416, 38)
component "MG90S | case envelope · measure actual ears" placed x (0.453154, -0.784886, -0.422618) y (0.211309, -0.365998, 0.906308) z (-0.866025, -0.5, 0) at (74.9869, -91.8812, 20.25)
component "07 | Tibia · tapered foot" placed x (-0.043578, 0.075479, -0.996195) y (0.866025, 0.5, 0) z (0.498097, -0.86273, -0.087156) at (58.5325, -101.3812, 20.25)
component "Stock double horn | reference only" placed x (-0.043578, 0.075479, -0.996195) y (0.498097, -0.86273, -0.087156) z (-0.866025, -0.5, 0) at (74.9869, -91.8812, 20.25)
component "HARDWARE | M2x8 servo ears · unthreaded reference" placed x (1, 0, 0) y (0, 1, 0) z (0, 0, 1) at (49, 0, 0)
component "HARDWARE | M1_6x8 stock horn · unthreaded reference" placed x (1, 0, 0) y (0, 1, 0) z (0, 0, 1) at (49, 0, 0)
component "HARDWARE | M3x10 countersunk hip · reference" placed x (1, 0, 0) y (0, 1, 0) z (0, 0, 1) at (49, 0, 0)
component "HARDWARE | M2x30 knee towers · unthreaded reference" placed x (0.906308, 0, -0.422618) y (0, 1, 0) z (0.422618, 0, 0.906308) at (79, 0, 38)
component "HARDWARE | M3x50 chassis stack · unthreaded reference" placed x (1, 0, 0) y (0, -1, 0) z (0, 0, -1) at (0, 0, 15)
component "HARDWARE | M2x8 servo ears · unthreaded reference" placed x (1, 0, 0) y (0, 0, -1) z (0, 1, 0) at (79, 0, 38)
component "HARDWARE | M1_6x8 stock horn · unthreaded reference" placed x (0.906308, 0, -0.422618) y (-0.422618, 0, -0.906308) z (0, 1, 0) at (79, 0, 38)
component "HARDWARE | M2x8 servo ears · unthreaded reference" placed x (0.906308, 0, -0.422618) y (0.422618, 0, 0.906308) z (0, -1, 0) at (117.0649, 19, 20.25)
component "HARDWARE | M1_6x8 stock horn · unthreaded reference" placed x (-0.087156, 0, -0.996195) y (0.996195, 0, -0.087156) z (0, -1, 0) at (117.0649, 19, 20.25)
component "HARDWARE | M2x8 servo ears · unthreaded reference" placed x (0.5, 0.866025, 0) y (-0.866025, 0.5, 0) z (0, 0, 1) at (24.5, 42.4352, 0)
component "HARDWARE | M1_6x8 stock horn · unthreaded reference" placed x (0.5, 0.866025, 0) y (-0.866025, 0.5, 0) z (0, 0, 1) at (24.5, 42.4352, 0)
component "HARDWARE | M2x8 servo ears · unthreaded reference" placed x (0.5, 0.866025, 0) y (0, 0, -1) z (-0.866025, 0.5, 0) at (39.5, 68.416, 38)
component "HARDWARE | M1_6x8 stock horn · unthreaded reference" placed x (0.453154, 0.784886, -0.422618) y (-0.211309, -0.365998, -0.906308) z (-0.866025, 0.5, 0) at (39.5, 68.416, 38)
component "HARDWARE | M2x8 servo ears · unthreaded reference" placed x (0.453154, 0.784886, -0.422618) y (0.211309, 0.365998, 0.906308) z (0.866025, -0.5, 0) at (42.078, 110.8812, 20.25)
component "HARDWARE | M1_6x8 stock horn · unthreaded reference" placed x (-0.043578, -0.075479, -0.996195) y (0.498097, 0.86273, -0.087156) z (0.866025, -0.5, 0) at (42.078, 110.8812, 20.25)
component "HARDWARE | M3x10 countersunk hip · reference" placed x (0.5, 0.866025, 0) y (-0.866025, 0.5, 0) z (0, 0, 1) at (24.5, 42.4352, 0)
component "HARDWARE | M2x30 knee towers · unthreaded reference" placed x (0.453154, 0.784886, -0.422618) y (-0.866025, 0.5, 0) z (0.211309, 0.365998, 0.906308) at (39.5, 68.416, 38)
component "HARDWARE | M2x8 servo ears · unthreaded reference" placed x (-0.5, 0.866025, 0) y (-0.866025, -0.5, 0) z (0, 0, 1) at (-24.5, 42.4352, 0)
component "HARDWARE | M1_6x8 stock horn · unthreaded reference" placed x (-0.5, 0.866025, 0) y (-0.866025, -0.5, 0) z (0, 0, 1) at (-24.5, 42.4352, 0)
component "HARDWARE | M2x8 servo ears · unthreaded reference" placed x (-0.5, 0.866025, 0) y (0, 0, -1) z (-0.866025, -0.5, 0) at (-39.5, 68.416, 38)
component "HARDWARE | M1_6x8 stock horn · unthreaded reference" placed x (-0.453154, 0.784886, -0.422618) y (0.211309, -0.365998, -0.906308) z (-0.866025, -0.5, 0) at (-39.5, 68.416, 38)
component "HARDWARE | M2x8 servo ears · unthreaded reference" placed x (-0.453154, 0.784886, -0.422618) y (-0.211309, 0.365998, 0.906308) z (0.866025, 0.5, 0) at (-74.9869, 91.8812, 20.25)
component "HARDWARE | M1_6x8 stock horn · unthreaded reference" placed x (0.043578, -0.075479, -0.996195) y (-0.498097, 0.86273, -0.087156) z (0.866025, 0.5, 0) at (-74.9869, 91.8812, 20.25)
component "HARDWARE | M3x10 countersunk hip · reference" placed x (-0.5, 0.866025, 0) y (-0.866025, -0.5, 0) z (0, 0, 1) at (-24.5, 42.4352, 0)
component "HARDWARE | M2x30 knee towers · unthreaded reference" placed x (-0.453154, 0.784886, -0.422618) y (-0.866025, -0.5, 0) z (-0.211309, 0.365998, 0.906308) at (-39.5, 68.416, 38)
component "HARDWARE | M2x8 servo ears · unthreaded reference" placed x (-1, 0, 0) y (0, -1, 0) z (0, 0, 1) at (-49, 0, 0)
component "HARDWARE | M1_6x8 stock horn · unthreaded reference" placed x (-1, 0, 0) y (0, -1, 0) z (0, 0, 1) at (-49, 0, 0)
component "HARDWARE | M2x8 servo ears · unthreaded reference" placed x (-1, 0, 0) y (0, 0, -1) z (0, -1, 0) at (-79, 0, 38)
component "HARDWARE | M1_6x8 stock horn · unthreaded reference" placed x (-0.906308, 0, -0.422618) y (0.422618, 0, -0.906308) z (0, -1, 0) at (-79, 0, 38)
component "HARDWARE | M2x8 servo ears · unthreaded reference" placed x (-0.906308, 0, -0.422618) y (-0.422618, 0, 0.906308) z (0, 1, 0) at (-117.0649, -19, 20.25)
component "HARDWARE | M1_6x8 stock horn · unthreaded reference" placed x (0.087156, 0, -0.996195) y (-0.996195, 0, -0.087156) z (0, 1, 0) at (-117.0649, -19, 20.25)
component "HARDWARE | M3x10 countersunk hip · reference" placed x (-1, 0, 0) y (0, -1, 0) z (0, 0, 1) at (-49, 0, 0)
component "HARDWARE | M2x30 knee towers · unthreaded reference" placed x (-0.906308, 0, -0.422618) y (0, -1, 0) z (-0.422618, 0, 0.906308) at (-79, 0, 38)
component "HARDWARE | M2x8 servo ears · unthreaded reference" placed x (-0.5, -0.866025, 0) y (0.866025, -0.5, 0) z (0, 0, 1) at (-24.5, -42.4352, 0)
component "HARDWARE | M1_6x8 stock horn · unthreaded reference" placed x (-0.5, -0.866025, 0) y (0.866025, -0.5, 0) z (0, 0, 1) at (-24.5, -42.4352, 0)
component "HARDWARE | M2x8 servo ears · unthreaded reference" placed x (-0.5, -0.866025, 0) y (0, 0, -1) z (0.866025, -0.5, 0) at (-39.5, -68.416, 38)
component "HARDWARE | M1_6x8 stock horn · unthreaded reference" placed x (-0.453154, -0.784886, -0.422618) y (0.211309, 0.365998, -0.906308) z (0.866025, -0.5, 0) at (-39.5, -68.416, 38)
component "HARDWARE | M2x8 servo ears · unthreaded reference" placed x (-0.453154, -0.784886, -0.422618) y (-0.211309, -0.365998, 0.906308) z (-0.866025, 0.5, 0) at (-42.078, -110.8812, 20.25)
component "HARDWARE | M1_6x8 stock horn · unthreaded reference" placed x (0.043578, 0.075479, -0.996195) y (-0.498097, -0.86273, -0.087156) z (-0.866025, 0.5, 0) at (-42.078, -110.8812, 20.25)
component "HARDWARE | M3x10 countersunk hip · reference" placed x (-0.5, -0.866025, 0) y (0.866025, -0.5, 0) z (0, 0, 1) at (-24.5, -42.4352, 0)
component "HARDWARE | M2x30 knee towers · unthreaded reference" placed x (-0.453154, -0.784886, -0.422618) y (0.866025, -0.5, 0) z (-0.211309, -0.365998, 0.906308) at (-39.5, -68.416, 38)
component "HARDWARE | M2x8 servo ears · unthreaded reference" placed x (0.5, -0.866025, 0) y (0.866025, 0.5, 0) z (0, 0, 1) at (24.5, -42.4352, 0)
component "HARDWARE | M1_6x8 stock horn · unthreaded reference" placed x (0.5, -0.866025, 0) y (0.866025, 0.5, 0) z (0, 0, 1) at (24.5, -42.4352, 0)
component "HARDWARE | M2x8 servo ears · unthreaded reference" placed x (0.5, -0.866025, 0) y (0, 0, -1) z (0.866025, 0.5, 0) at (39.5, -68.416, 38)
component "HARDWARE | M1_6x8 stock horn · unthreaded reference" placed x (0.453154, -0.784886, -0.422618) y (-0.211309, 0.365998, -0.906308) z (0.866025, 0.5, 0) at (39.5, -68.416, 38)
component "HARDWARE | M2x8 servo ears · unthreaded reference" placed x (0.453154, -0.784886, -0.422618) y (0.211309, -0.365998, 0.906308) z (-0.866025, -0.5, 0) at (74.9869, -91.8812, 20.25)
component "HARDWARE | M1_6x8 stock horn · unthreaded reference" placed x (-0.043578, 0.075479, -0.996195) y (0.498097, -0.86273, -0.087156) z (-0.866025, -0.5, 0) at (74.9869, -91.8812, 20.25)
component "HARDWARE | M3x10 countersunk hip · reference" placed x (0.5, -0.866025, 0) y (0.866025, 0.5, 0) z (0, 0, 1) at (24.5, -42.4352, 0)
component "HARDWARE | M2x30 knee towers · unthreaded reference" placed x (0.453154, -0.784886, -0.422618) y (0.866025, 0.5, 0) z (0.211309, -0.365998, 0.906308) at (39.5, -68.416, 38)
component "CORE | GuardLower" placed x (1, 0, 0) y (0, 1, 0) z (0, 0, 1) at (-36.3731, 21, 0)
component "CORE | GuardUpper" placed x (1, 0, 0) y (0, 1, 0) z (0, 0, 1) at (-36.3731, 21, 0)
component "CORE | GuardLower" placed x (1, 0, 0) y (0, 1, 0) z (0, 0, 1) at (-36.3731, -21, 0)
component "CORE | GuardUpper" placed x (1, 0, 0) y (0, 1, 0) z (0, 0, 1) at (-36.3731, -21, 0)
component "CORE | GuardTall" placed x (1, 0, 0) y (0, 1, 0) z (0, 0, 1) at (0, -42, 0)
component "CORE | GuardLower" placed x (1, 0, 0) y (0, 1, 0) z (0, 0, 1) at (36.3731, -21, 0)
component "CORE | GuardUpper" placed x (1, 0, 0) y (0, 1, 0) z (0, 0, 1) at (36.3731, -21, 0)
component "PCA9685 #815 | 0x40" placed x (1, 0, 0) y (0, 1, 0) z (0, 0, 1) at (0, 0, 0)
component "PCA9685 #815 | 0x41" placed x (1, 0, 0) y (0, 1, 0) z (0, 0, 1) at (0, 0, 0)
component "BRAIN | Adafruit Feather ESP32 V2 #5400" placed x (1, 0, 0) y (0, 1, 0) z (0, 0, 1) at (0, 0, 0)
component "POWER | Pololu D42V110F5 #5671" placed x (1, 0, 0) y (0, 1, 0) z (0, 0, 1) at (0, 0, 0)
component "POWER | Pololu D24V10F5 #2831" placed x (1, 0, 0) y (0, 1, 0) z (0, 0, 1) at (0, 0, 0)
component "BATTERY | Gens ace 450mAh 2S XT30 · pouch envelope" placed x (1, 0, 0) y (0, 1, 0) z (0, 0, 1) at (0, 0, 0)
component "HARDWARE | PCA M2x14 · unthreaded reference" placed x (1, 0, 0) y (0, 1, 0) z (0, 0, 1) at (0, 0, 0)
component "HARDWARE | Feather M2x12 · unthreaded reference" placed x (1, 0, 0) y (0, 1, 0) z (0, 0, 1) at (0, 0, 0)
component "HARDWARE | Servo buck M2x10 · unthreaded reference" placed x (1, 0, 0) y (0, 1, 0) z (0, 0, 1) at (0, 0, 0)
component "HARDWARE | Core M2x50 · unthreaded reference" placed x (1, 0, 0) y (0, 1, 0) z (0, 0, 1) at (0, 0, 0)
equation "hx_yaw_radius = 49.0 mm" comment "Builder design reference; rebuild for dimension changes"
equation "hx_coxa = 30.0 mm" comment "Builder design reference; rebuild for dimension changes"
equation "hx_femur = 42.0 mm" comment "Builder design reference; rebuild for dimension changes"
equation "hx_tibia = 80.0 mm" comment "Builder design reference; rebuild for dimension changes"
equation "hx_shoulder_z = 38.0 mm" comment "Builder design reference; rebuild for dimension changes"
equation "hx_femur_angle = -25.0 deg" comment "Builder design reference; rebuild for dimension changes"
equation "hx_tibia_angle = -95.0 deg" comment "Builder design reference; rebuild for dimension changes"
equation "hx_plate = 3.0 mm" comment "Builder design reference; rebuild for dimension changes"
equation "hx_servo_width = 12.4 mm" comment "Builder design reference; rebuild for dimension changes"
equation "hx_servo_length = 22.8 mm" comment "Builder design reference; rebuild for dimension changes"
equation "hx_servo_height = 28.5 mm" comment "Builder design reference; rebuild for dimension changes"
named bodies: "Chassis", "LowerDeck", "PowerShelf", "ElectronicsDeck", "LowerSpacer", "UpperSpacer", "GuardLower", "GuardUpper", "GuardTall", "CoreBridge", "CoreCap", "CoxaPlate", "HipBracket", "FemurPlate", "KneeMount", "Tibia", "FitCoupon", "M2x8 servo ears bolt 1", "M2x8 servo ears nut 1", "M2x8 servo ears bolt 2", "M2x8 servo ears nut 2", "M1_6x8 stock horn bolt 1", "M1_6x8 stock horn nut 1", "M1_6x8 stock horn bolt 2", "M1_6x8 stock horn nut 2", "M2x30 knee towers bolt 1", "M2x30 knee towers nut 1", "M2x30 knee towers bolt 2", "M2x30 knee towers nut 2", "M3x50 chassis stack bolt 1", "M3x50 chassis stack nut 1", "M3x50 chassis stack bolt 2", "M3x50 chassis stack nut 2", "M3x50 chassis stack bolt 3", "M3x50 chassis stack nut 3", "M3x50 chassis stack bolt 4", "M3x50 chassis stack nut 4", "M3x50 chassis stack bolt 5", "M3x50 chassis stack nut 5", "M3x50 chassis stack bolt 6", "M3x50 chassis stack nut 6", "PCA M2x14 bolt 1", "PCA M2x14 nut 1", "PCA M2x14 bolt 2", "PCA M2x14 nut 2", "PCA M2x14 bolt 3", "PCA M2x14 nut 3", "PCA M2x14 bolt 4", "PCA M2x14 nut 4", "PCA M2x14 bolt 5", "PCA M2x14 nut 5", "PCA M2x14 bolt 6", "PCA M2x14 nut 6", "PCA M2x14 bolt 7", "PCA M2x14 nut 7", "PCA M2x14 bolt 8", "PCA M2x14 nut 8", "Feather M2x12 bolt 1", "Feather M2x12 nut 1", "Feather M2x12 bolt 2", "Feather M2x12 nut 2", "Feather M2x12 bolt 3", "Feather M2x12 nut 3", "Feather M2x12 bolt 4", "Feather M2x12 nut 4", "Servo buck M2x8 bolt 1", "Servo buck M2x8 nut 1", "Servo buck M2x8 bolt 2", "Servo buck M2x8 nut 2", "Servo buck M2x8 bolt 3", "Servo buck M2x8 nut 3", "Servo buck M2x8 bolt 4", "Servo buck M2x8 nut 4", "Core M2x50 bolt 1", "Core M2x50 nut 1", "Core M2x50 bolt 2", "Core M2x50 nut 2", "Core M2x50 bolt 3", "Core M2x50 nut 3", "Core M2x50 bolt 4", "Core M2x50 nut 4", "Core M2x50 bolt 5", "Core M2x50 nut 5", "Core M2x50 bolt 6", "Core M2x50 nut 6"
